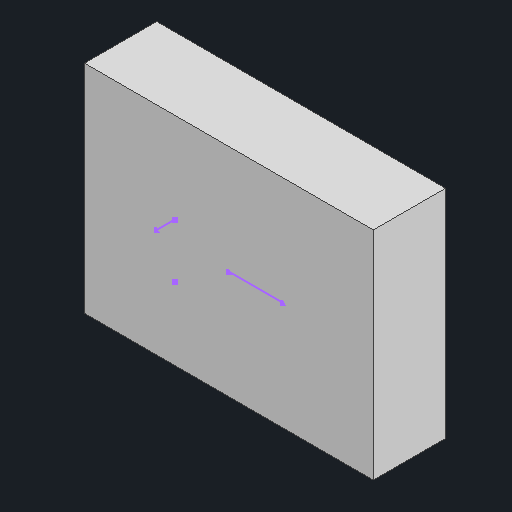
# Autodesk Inventor part: viewport-selection-solid
Saved by Autodesk Inventor 2027 (Build 310192060, 192F)
## iProperties
Created: 2026-11-18
Part Number: viewport-selection-solid
Material: Generic
Document SubType Name: Modeling
Designer: vmiguel
Density: 1 g/cm^3
Appearance: Default
Author: vmiguel
Autodesk Inventor part; units mm, degrees
ref_plane "YZ Plane" through (0, 0, 0) normal (1, 0, 0) x (0, 1, 0)
ref_plane "XZ Plane" through (0, 0, 0) normal (0, 1, 0) x (-1, 0, 0)
ref_plane "XY Plane" through (0, 0, 0) normal (0, 0, 1) x (1, 0, 0)
sketch "Sketch1" plane through (0, 0, 0) normal (0, 0, 1) x (1, 0, 0)
  line L0 (-40, -30) -> (40, -30)
  line L1 (40, -30) -> (40, 30)
  line L2 (40, 30) -> (-40, 30)
  line L3 (-40, 30) -> (-40, -30)
  constraints: 8 end point, 2 parallel, 1 horizontal, 1 perpendicular
extrude "Extrusion1" add sketch "Sketch1" along normal blind 20
sketch "Sketch2" plane through (-40, -30, 0) normal (-1, 0, 0) x (0, 0, 1)
  point P0 (10, 5)
sketch3d "3D Sketch1"
sketch3d "3D Sketch6"
body "Solid1"
